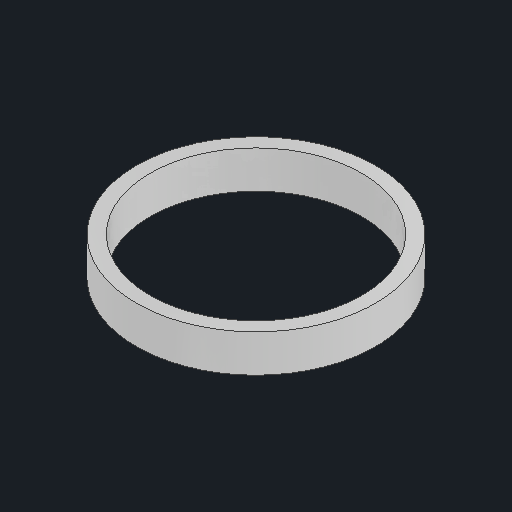
# Autodesk Inventor part: dec_setting_circle
Saved by Autodesk Inventor 2027.1 (Build 311270010, 270A)
## iProperties
Created: 2026-11-03
Part Number: dec_setting_circle
Material: Generic
Description: Dec setting circle (degrees)
Document SubType Name: Modeling
Designer: Claude (from photos)
Density: 1 g/cm^3
Appearance: Aluminum - Polished
Author: alexg
Autodesk Inventor part; units mm, degrees
ref_plane "YZ Plane" through (0, 0, 0) normal (1, 0, 0) x (0, 1, 0)
ref_plane "XY Plane" through (0, 0, 0) normal (0, 0, 1) x (1, 0, 0)
ref_plane "Work Plane1" through (0, -45, 0) normal (0, 1, 0) x (-1, 0, 0)
sketch "Dec setting circle sketch" plane through (0, -45, 0) normal (0, 1, 0) x (-1, 0, 0)
  circle A0 centre (-187, 0) radius 35
  circle A1 centre (-187, 0) radius 31
  constraints: 2 centre point
extrude "Dec setting circle" add sketch "Dec setting circle sketch" against normal blind 11
body "Solid1"
